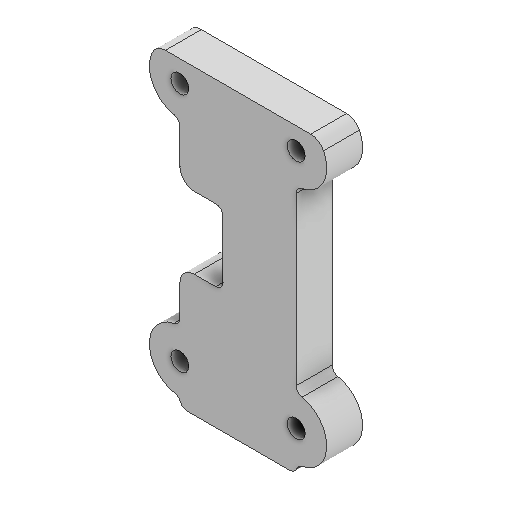
# Autodesk Inventor part: 3DP_PLA_CANable_Mounting_Plate
Saved by Autodesk Inventor 2027 (Build 310192060, 192F)
## iProperties
Created: 2026-02-11
Part Number: 3DP_PLA_CANable_Mounting_Plate
Material: Generic
Document SubType Name: Modeling
Designer: User
Density: 1 g/cm^3
Appearance: Default
Author: User
Autodesk Inventor part; units mm, degrees
ref_plane "YZ Plane" through (0, 0, 0) normal (1, 0, 0) x (0, 1, 0)
ref_plane "XZ Plane" through (0, 0, 0) normal (0, 1, 0) x (-1, 0, 0)
ref_plane "XY Plane" through (0, 0, 0) normal (0, 0, 1) x (1, 0, 0)
sketch "Sketch1" plane through (0, 0, 0) normal (0, 0, 1) x (1, 0, 0)
  line L0 (8.1, 25) -> (-8.1, 25)
  line L1 (-8.1, 25) -> (-8.1, -25)
  line L2 (-8.1, -25) -> (8.1, -25)
  line L3 (8.1, -25) -> (8.1, 25)
  circle A0 centre (8.1, 14) radius 1.25
  circle A1 centre (-8.1, 14) radius 1.25
  circle A2 centre (-8.1, -19.5) radius 1.25
  circle A3 centre (8.1, -19.5) radius 1.25
  circle A4 centre (8.1, 14) radius 4.25
  circle A5 centre (8.1, -19.5) radius 4.25
  circle A6 centre (-8.1, 14) radius 4.25
  circle A7 centre (-8.1, -19.5) radius 4.25
  point P0 (0, 0)
  point P1 (0, 0)
  point P2 (-8.1, 9.75)
  point P3 (-8.1, -15.25)
  point P4 (-8.1, -23.75)
  point P5 (8.1, -23.75)
  point P6 (8.1, -15.25)
  point P7 (8.1, 9.75)
  point P8 (8.1, 18.25)
  point P9 (-8.1, 18.25)
  dimension "d0" = 50
  dimension "d1" = 16.2
  dimension "d2" = 8.1
  dimension "d3" = 25
  dimension "d4" = 11
  dimension "d5" = 2.5
  dimension "d6" = 2.5
  dimension "d7" = 5.5
  dimension "d8" = 5.5
  dimension "d9" = 2.5
  dimension "d10" = 2.5
  dimension "d11" = 3
  dimension "d12" = 3
  dimension "d13" = 3
  dimension "d14" = 3
  constraints: 8 centre point, 8 end point, 5 coincident, 4 point on line, 2 parallel, 1 horizontal, 1 horizontal alignment, 1 perpendicular
  measures "d0" distance of L2.end L0.start
  measures "d1" distance of L0.start L0.end
  measures "d2" distance from line of point (0, 0) L3
  measures "d3" distance from line of L0 point (0, 0)
  measures "d4" distance from line of point (8.1, 14) L0
  measures "d5" diameter of A0
  measures "d6" diameter of A1
  measures "d7" distance from line of L2 point (8.1, -19.5)
  measures "d8" distance from line of L2 point (-8.1, -19.5)
  measures "d9" diameter of A2
  measures "d10" diameter of A3
  measures "d11" radial gap between concentric circles of A0 A4
  measures "d12" radial gap between concentric circles of A3 A5
  measures "d13" radial gap between concentric circles of A1 A6
  measures "d14" radial gap between concentric circles of A2 A7
extrude "Extrusion1" add sketch "Sketch1" along normal blind 5 contours L3 A4 A5 L2 L1 A7 A6 L0 | A4 L3 A0 | L3 A0 A4 | A6 L1 A1 | L1 A1 A6 | A5 L3 A3 | L3 A3 A5 | A7 L1 A2 | L1 A2 A7
sketch "Sketch2" plane through (0, 0, 5) normal (0, 0, 1) x (1, 0, 0)
  arc A0 (-8.1, -15.25) -> (-8.1, -23.75) centre (-8.1, -19.5) ccw projected
  line L0 (-8.1, -23.75) -> (-8.1, -25) projected
  line L1 (-8.1, -25) -> (8.1, -25) projected
  line L2 (8.1, -25) -> (8.1, -23.75) projected
  arc A1 (8.1, -23.75) -> (8.1, -15.25) centre (8.1, -19.5) ccw projected
  line L3 (8.1, -15.25) -> (8.1, 9.75) projected
  arc A2 (8.1, 9.75) -> (8.1, 18.25) centre (8.1, 14) ccw projected
  line L4 (8.1, 18.25) -> (8.1, 25) projected
  line L5 (8.1, 25) -> (-8.1, 25) projected
  line L6 (-8.1, 25) -> (-8.1, 18.25) projected
  arc A3 (-8.1, 18.25) -> (-8.1, 9.75) centre (-8.1, 14) ccw projected
  line L7 (-8.1, 9.75) -> (-8.1, -15.25) projected
  circle A4 centre (8.1, 14) radius 1.25 projected
  circle A5 centre (8.1, -19.5) radius 1.25 projected
  circle A6 centre (-8.1, 14) radius 1.25 projected
  circle A7 centre (-8.1, -19.5) radius 1.25 projected
  line L8 (-8.1, 17) -> (8.1, 17)
  line L9 (-8.1, 17) -> (-11.1104, 17)
  line L10 (8.1, 17) -> (11.1104, 17)
  line L11 (-8.1, 1) -> (-3.1, 1)
  line L12 (-3.1, 1) -> (-3.1, -7)
  line L13 (-3.1, -7) -> (-8.1, -7)
  line L14 (-8.1, 2) -> (-2.1, 2)
  line L15 (-2.1, 2) -> (-2.1, -8)
  line L16 (-2.1, -8) -> (-8.1, -8)
  point P0 (0, 0)
  dimension "d17" = 42
  dimension "d18" = 5
  dimension "d19" = 18
  dimension "d20" = 8
  dimension "d21" = 1
  constraints: 18 end point, 4 perpendicular, 4 point on line, 2 horizontal, 2 point on circle, 2 other
  measures "d17" distance between parallel lines of L1 L8
  measures "d18" distance between parallel lines of L7 L12
  measures "d19" distance between parallel lines of L1 L13
  measures "d20" distance between parallel lines of L11 L13
  measures "d21" distance between parallel lines of L11 L14
extrude "Extrusion2" cut sketch "Sketch2" against normal blind 5 contours L7 L13 L12 L11 L14 L15 L16 | L7 L11 L12 L13 | A3 L6 L5 L4 A2 L10 L8 L9
fillet "Fillet1" radius 2 2 edges at (-11.1104, 17, 2.5) (11.1104, 17, 2.5)
fillet "Fillet2" radius 2 2 edges at (-8.1, 2, 2.5) (-8.1, -8, 2.5)
fillet "Fillet3" radius 1 2 edges at (-2.1, 2, 2.5) (-2.1, -8, 2.5)
fillet "Fillet4" radius 1 8 edges at (-8.1, -23.75, 2.5) (-8.1, -25, 2.5) (8.1, -25, 2.5) (8.1, -23.75, 2.5) (8.1, -15.25, 2.5) (-8.1, -15.25, 2.5) (-8.1, 9.75, 2.5) (8.1, 9.75, 2.5)
sketch "Sketch3" plane through (0, 0, 0) normal (0, 0, -1) x (-1, 0, 0)
  circle A0 centre (8.1, -19.5) radius 1.25 projected
  circle A1 centre (8.1, 14) radius 1.25 projected
  circle A2 centre (-8.1, -19.5) radius 1.25 projected
  circle A3 centre (-8.1, 14) radius 1.25 projected
  arc A4 (-8.155, -24.3269) -> (-7.2099, -25) centre (-7.2099, -24) ccw projected
  line L0 (7.1, -25) -> (-7.2099, -25) projected
  arc A5 (7.1, -25) -> (8.0413, -24.3376) centre (7.1, -24) ccw projected
  arc A6 (8.8144, -23.6895) -> (8.0413, -24.3376) centre (8.9825, -24.6753) ccw projected
  arc A7 (8.8144, -23.6895) -> (8.9095, -15.3278) centre (8.1, -19.5) ccw projected
  arc A8 (8.1, -14.3461) -> (8.9095, -15.3278) centre (9.1, -14.3461) ccw projected
  line L1 (8.1, -10) -> (8.1, -14.3461) projected
  arc A9 (8.1, -10) -> (6.1, -8) centre (6.1, -10) ccw projected
  line L2 (6.1, -8) -> (3.1, -8) projected
  arc A10 (2.1, -7) -> (3.1, -8) centre (3.1, -7) ccw projected
  line L3 (2.1, -7) -> (2.1, 1) projected
  arc A11 (3.1, 2) -> (2.1, 1) centre (3.1, 1) ccw projected
  line L4 (3.1, 2) -> (6.1, 2) projected
  arc A12 (6.1, 2) -> (8.1, 4) centre (6.1, 4) ccw projected
  line L5 (8.1, 8.8461) -> (8.1, 4) projected
  arc A13 (8.9095, 9.8278) -> (8.1, 8.8461) centre (9.1, 8.8461) ccw projected
  arc A14 (8.9095, 9.8278) -> (11.9072, 15.8889) centre (8.1, 14) ccw projected
  arc A15 (11.9072, 15.8889) -> (10.1156, 17) centre (10.1156, 15) ccw projected
  line L6 (10.1156, 17) -> (-10.1156, 17) projected
  arc A16 (-10.1156, 17) -> (-11.9072, 15.8889) centre (-10.1156, 15) ccw projected
  arc A17 (-11.9072, 15.8889) -> (-8.9095, 9.8278) centre (-8.1, 14) ccw projected
  arc A18 (-8.1, 8.8461) -> (-8.9095, 9.8278) centre (-9.1, 8.8461) ccw projected
  line L7 (-8.1, -14.3461) -> (-8.1, 8.8461) projected
  arc A19 (-8.9095, -15.3278) -> (-8.1, -14.3461) centre (-9.1, -14.3461) ccw projected
  arc A20 (-8.9095, -15.3278) -> (-8.9095, -23.6722) centre (-8.1, -19.5) ccw projected
  arc A21 (-8.155, -24.3269) -> (-8.9095, -23.6722) centre (-9.1, -24.6539) ccw projected
  line L8 (6, -25) -> (6, -17)
  line L9 (6, -17) -> (-6, -17)
  line L10 (-6, -17) -> (-6, -25)
  point P0 (0, 0)
  dimension "d29" = 8
  dimension "d31" = 12
  dimension "d32" = 16.2
  dimension "d33" = 2.1
  constraints: 6 end point, 2 perpendicular, 2 point on line, 1 vertical
  measures "d29" distance between parallel lines of L0 L9
  measures "d31" distance between parallel lines of L10 L8
  measures "d32" distance between parallel lines of L7 L1
  measures "d33" distance between parallel lines of L1 L8
extrude "Extrusion3" cut sketch "Sketch3" against normal blind 0.75 contours L10 L9 L8 L0
fillet "Fillet5" radius 1 4 edges at (-6, -17, 0.375) (6, -17, 0.375) (-6, -25, 0.375) (6, -25, 0.375)
equation "\"d2\" = 0.5 * d1"
equation "\"d3\" = 0.5 * d0"
equation "\"d6\" = d5"
equation "\"d8\" = d7"
equation "\"d9\" = d5"
equation "\"d10\" = d5"
equation "\"d33\" = -0.5 * d31 + 0.5 * d32"
body "Solid1"
